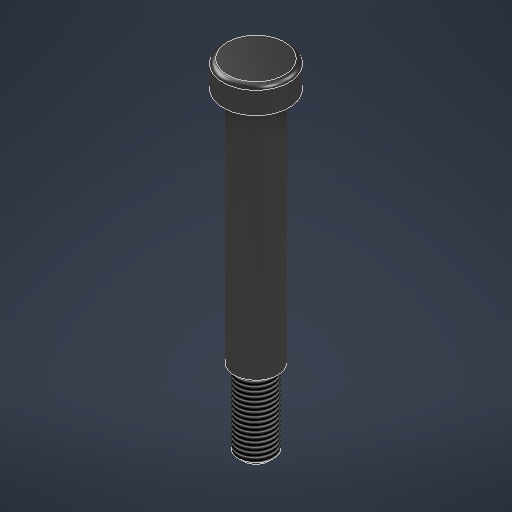
# Autodesk Inventor part: Cylinder Shaft
Saved by Autodesk Inventor 2026.3 (Build 303398000, 398)
## iProperties
Created: 2026-11-02
Part Number: Cylinder Shaft
Material: Steel
Document SubType Name: Modeling
Designer: ADMIN
Density: 7.85 g/cm^3
Appearance: Glossy - Black
Author: ADMIN
Autodesk Inventor part; units mm, degrees
ref_plane "YZ Plane" through (0, 0, 0) normal (1, 0, 0) x (0, 1, 0)
ref_plane "XZ Plane" through (0, 0, 0) normal (0, 1, 0) x (-1, 0, 0)
ref_plane "XY Plane" through (0, 0, 0) normal (0, 0, 1) x (1, 0, 0)
sketch "Sketch2" plane through (0, 0, 0) normal (0, 0, 1) x (1, 0, 0)
  line L0 (0, 47.5) -> (0, -2.5) construction
  line L1 (0, 39) -> (-3.75, 39)
  line L2 (-3.75, 39) -> (-3.75, 36)
  line L3 (-3.75, 36) -> (-2.5, 36)
  line L4 (-2.5, 36) -> (-2.5, 9)
  line L5 (-2.5, 9) -> (-2, 9)
  line L6 (-2, 9) -> (-2, 0)
  line L7 (-2, 0) -> (0, 0)
  line L8 (0, 39) -> (0, 0)
  point P0 (-2.5, 22.5)
  point P1 (0, 22.5)
  dimension "d12" = 50
  dimension "d13" = 3
  dimension "d14" = 27
  dimension "d15" = 9
  dimension "d16" = 4
  dimension "d17" = 5
  dimension "d18" = 7.5
  constraints: 18 end point, 6 perpendicular, 2 midpoint, 2 point on line, 1 coincident, 1 collinear, 1 horizontal, 1 horizontal alignment, 1 vertical
  measures "d12" distance of L0.start L0.end
  measures "d13" distance of L1.end L2.end
  measures "d14" distance of L3.end L4.end
  measures "d15" distance of L5.end L6.end
  measures "d16" diameter of L6 L0
  measures "d17" diameter of L4 L0
  measures "d18" diameter of L2 L0
revolve "Revolution1" add sketch "Sketch2" angle 360 about axis through (0, 47.5, 0) along (0, -1, 0)
fillet "Fillet1" radius 0.5 1 edges at (3.75, 39, 0)
chamfer "Chamfer1" distance 0.5 angle 45 1 edges at (2, 0, 0)
thread "Thread1" size "M4x0.5" class "6g" standard "ANSI Metric M Profile" full length
body "Solid1"
